Autodesk Fusion 360 part; units mm, degrees
(part 7 of 10)
sketch "Vertical bracket leg sketch (8)" plane through (0, 0, 17) normal (0, 0, 1) x (1, 0, 0) in component "METAL in-bay corner 11R"
  line L0 (215, 200) -> (218, 200)
  line L1 (218, 200) -> (218, 218)
  line L2 (218, 218) -> (215, 218)
  line L3 (215, 218) -> (215, 200)
  dimension "d2836" = 215
  dimension "d2837" = 200
  dimension "d2838" = 3
  dimension "d2839" = 18
  constraint horizontal L0
  constraint vertical L1
  constraint horizontal L2
  constraint vertical L3
  measures "d2836" horizontal distance of origin L0.start
  measures "d2837" vertical distance of origin L0.start
  measures "d2838" horizontal distance of L0.start L0.end
  measures "d2839" vertical distance of L0.end L1.end
extrude "Vertical bracket leg'''''''" add sketch "Vertical bracket leg sketch (8)" along normal blind 16 separate body makes body 92 in component "METAL in-bay corner 11R"
ref_plane "WorkPlane2" through (0, 0, 17) normal (0, 0, 1) x (1, 0, 0) in component "METAL in-bay corner 11R"
sketch "Horizontal bracket leg sketch (8)" plane through (0, 0, 17) normal (0, 0, 1) x (1, 0, 0) in component "METAL in-bay corner 11R"
  line L0 (200, 215) -> (218, 215)
  line L1 (218, 215) -> (218, 218)
  line L2 (218, 218) -> (200, 218)
  line L3 (200, 218) -> (200, 215)
  dimension "d2844" = 200
  dimension "d2845" = 215
  dimension "d2846" = 18
  dimension "d2847" = 3
  constraint horizontal L0
  constraint vertical L1
  constraint horizontal L2
  constraint vertical L3
  measures "d2844" horizontal distance of origin L0.start
  measures "d2845" vertical distance of origin L0.start
  measures "d2846" horizontal distance of L0.start L0.end
  measures "d2847" vertical distance of L0.end L1.end
extrude "Horizontal bracket leg'''''''" add sketch "Horizontal bracket leg sketch (8)" along normal blind 16 bodies 92 in component "METAL in-bay corner 11R"
ref_plane "WorkPlane3" through (218, 0, 0) normal (1, 0, 0) x (0, 1, 0) in component "METAL in-bay corner 11R"
sketch "Vertical rail bolt sketch (8)" plane through (218, 0, 0) normal (1, 0, 0) x (0, 0, -1) in component "METAL in-bay corner 11R"
  circle A0 centre (-25, 206) radius 2.75
  dimension "d2852" = 25
  dimension "d2853" = 206
  dimension "d2854" = 5.5
  measures "d2852" horizontal distance of origin A0.centre
  measures "d2853" vertical distance of origin A0.centre
  measures "d2854" diameter of A0
extrude "Vertical rail bolt'''''''" cut sketch "Vertical rail bolt sketch (8)" against normal blind 3 bodies 92 in component "METAL in-bay corner 11R"
ref_plane "WorkPlane4" through (0, 218, 0) normal (0, 1, 0) x (0, 0, 1) in component "METAL in-bay corner 11R"
sketch "Tie bolt sketch (8)" plane through (0, 218, 0) normal (0, 1, 0) x (1, 0, 0) in component "METAL in-bay corner 11R"
  circle A0 centre (206, -25) radius 2.75
  dimension "d2859" = 206
  dimension "d2860" = 25
  dimension "d2861" = 5.5
  measures "d2859" horizontal distance of origin A0.centre
  measures "d2860" vertical distance of origin A0.centre
  measures "d2861" diameter of A0
extrude "Tie bolt'''''''" cut sketch "Tie bolt sketch (8)" against normal blind 3 bodies 92 in component "METAL in-bay corner 11R"
ref_plane "WorkPlane1" through (215, 0, 0) normal (1, 0, 0) x (0, 1, 0) in component "REFERENCE side M5x8 11R X"
sketch "Button head envelope sketch (24)" plane through (215, 0, 0) normal (1, 0, 0) x (0, 0, -1) in component "REFERENCE side M5x8 11R X"
  circle A0 centre (-25, 206) radius 4.75
  dimension "d2866" = 25
  dimension "d2867" = 206
  dimension "d2868" = 9.5
  measures "d2866" horizontal distance of origin A0.centre
  measures "d2867" vertical distance of origin A0.centre
  measures "d2868" diameter of A0
extrude "Button head envelope'''''''''''''''''''''''" add sketch "Button head envelope sketch (24)" against normal blind 3 separate body makes body 93 in component "REFERENCE side M5x8 11R X"
ref_plane "WorkPlane2" through (215, 0, 0) normal (1, 0, 0) x (0, 1, 0) in component "REFERENCE side M5x8 11R X"
sketch "Shank envelope sketch (24)" plane through (215, 0, 0) normal (1, 0, 0) x (0, 0, -1) in component "REFERENCE side M5x8 11R X"
  circle A0 centre (-25, 206) radius 2.5
  dimension "d2873" = 25
  dimension "d2874" = 206
  dimension "d2875" = 5
  measures "d2873" horizontal distance of origin A0.centre
  measures "d2874" vertical distance of origin A0.centre
  measures "d2875" diameter of A0
extrude "Shank envelope'''''''''''''''''''''''" add sketch "Shank envelope sketch (24)" along normal blind 8 bodies 93 in component "REFERENCE side M5x8 11R X"
ref_plane "WorkPlane1" through (0, 0, 20.6) normal (0, 0, 1) x (1, 0, 0) in component "REFERENCE thin METAL channel nut side 11R X"
sketch "Thin nut envelope sketch (24)" plane through (0, 0, 20.6) normal (0, 0, 1) x (1, 0, 0) in component "REFERENCE thin METAL channel nut side 11R X"
  line L0 (219.5, 200) -> (222.2, 200)
  line L1 (222.2, 200) -> (222.2, 212)
  line L2 (222.2, 212) -> (219.5, 212)
  line L3 (219.5, 212) -> (219.5, 200)
  dimension "d2880" = 219.5
  dimension "d2881" = 200
  dimension "d2882" = 2.7
  dimension "d2883" = 12
  constraint horizontal L0
  constraint vertical L1
  constraint horizontal L2
  constraint vertical L3
  measures "d2880" horizontal distance of origin L0.start
  measures "d2881" vertical distance of origin L0.start
  measures "d2882" horizontal distance of L0.start L0.end
  measures "d2883" vertical distance of L0.end L1.end
extrude "Thin nut envelope'''''''''''''''''''''''" add sketch "Thin nut envelope sketch (24)" along normal blind 8.8 separate body makes body 94 in component "REFERENCE thin METAL channel nut side 11R X"
ref_plane "WorkPlane2" through (219.5, 0, 0) normal (1, 0, 0) x (0, 1, 0) in component "REFERENCE thin METAL channel nut side 11R X"
sketch "Thread envelope sketch (24)" plane through (219.5, 0, 0) normal (1, 0, 0) x (0, 0, -1) in component "REFERENCE thin METAL channel nut side 11R X"
  circle A0 centre (-25, 206) radius 2.6
  dimension "d2888" = 25
  dimension "d2889" = 206
  dimension "d2890" = 5.2
  measures "d2888" horizontal distance of origin A0.centre
  measures "d2889" vertical distance of origin A0.centre
  measures "d2890" diameter of A0
extrude "Thread envelope'''''''''''''''''''''''" cut sketch "Thread envelope sketch (24)" along normal blind 2.7 bodies 94 in component "REFERENCE thin METAL channel nut side 11R X"
ref_plane "WorkPlane1" through (0, 215, 0) normal (0, 1, 0) x (0, 0, 1) in component "REFERENCE side M5x8 11R Y"
sketch "Button head envelope sketch (25)" plane through (0, 215, 0) normal (0, 1, 0) x (1, 0, 0) in component "REFERENCE side M5x8 11R Y"
  circle A0 centre (206, -25) radius 4.75
  dimension "d2895" = 206
  dimension "d2896" = 25
  dimension "d2897" = 9.5
  measures "d2895" horizontal distance of origin A0.centre
  measures "d2896" vertical distance of origin A0.centre
  measures "d2897" diameter of A0
extrude "Button head envelope''''''''''''''''''''''''" add sketch "Button head envelope sketch (25)" against normal blind 3 separate body makes body 95 in component "REFERENCE side M5x8 11R Y"
ref_plane "WorkPlane2" through (0, 215, 0) normal (0, 1, 0) x (0, 0, 1) in component "REFERENCE side M5x8 11R Y"
sketch "Shank envelope sketch (25)" plane through (0, 215, 0) normal (0, 1, 0) x (1, 0, 0) in component "REFERENCE side M5x8 11R Y"
  circle A0 centre (206, -25) radius 2.5
  dimension "d2902" = 206
  dimension "d2903" = 25
  dimension "d2904" = 5
  measures "d2902" horizontal distance of origin A0.centre
  measures "d2903" vertical distance of origin A0.centre
  measures "d2904" diameter of A0
extrude "Shank envelope''''''''''''''''''''''''" add sketch "Shank envelope sketch (25)" along normal blind 8 bodies 95 in component "REFERENCE side M5x8 11R Y"
ref_plane "WorkPlane1" through (0, 0, 20.6) normal (0, 0, 1) x (1, 0, 0) in component "REFERENCE thin METAL channel nut side 11R Y"
sketch "Thin nut envelope sketch (25)" plane through (0, 0, 20.6) normal (0, 0, 1) x (1, 0, 0) in component "REFERENCE thin METAL channel nut side 11R Y"
  line L0 (200, 219.5) -> (212, 219.5)
  line L1 (212, 219.5) -> (212, 222.2)
  line L2 (212, 222.2) -> (200, 222.2)
  line L3 (200, 222.2) -> (200, 219.5)
  dimension "d2909" = 200
  dimension "d2910" = 219.5
  dimension "d2911" = 12
  dimension "d2912" = 2.7
  constraint horizontal L0
  constraint vertical L1
  constraint horizontal L2
  constraint vertical L3
  measures "d2909" horizontal distance of origin L0.start
  measures "d2910" vertical distance of origin L0.start
  measures "d2911" horizontal distance of L0.start L0.end
  measures "d2912" vertical distance of L0.end L1.end
extrude "Thin nut envelope''''''''''''''''''''''''" add sketch "Thin nut envelope sketch (25)" along normal blind 8.8 separate body makes body 96 in component "REFERENCE thin METAL channel nut side 11R Y"
ref_plane "WorkPlane2" through (0, 219.5, 0) normal (0, 1, 0) x (0, 0, 1) in component "REFERENCE thin METAL channel nut side 11R Y"
sketch "Thread envelope sketch (25)" plane through (0, 219.5, 0) normal (0, 1, 0) x (1, 0, 0) in component "REFERENCE thin METAL channel nut side 11R Y"
  circle A0 centre (206, -25) radius 2.6
  dimension "d2917" = 206
  dimension "d2918" = 25
  dimension "d2919" = 5.2
  measures "d2917" horizontal distance of origin A0.centre
  measures "d2918" vertical distance of origin A0.centre
  measures "d2919" diameter of A0
extrude "Thread envelope''''''''''''''''''''''''" cut sketch "Thread envelope sketch (25)" along normal blind 2.7 bodies 96 in component "REFERENCE thin METAL channel nut side 11R Y"
ref_plane "WorkPlane1" through (0, 0, 15) normal (0, 0, 1) x (1, 0, 0) in component "METAL flush wall tab 00"
sketch "Side attachment leg sketch" plane through (0, 0, 15) normal (0, 0, 1) x (1, 0, 0) in component "METAL flush wall tab 00"
  line L0 (22, 68) -> (25, 68)
  line L1 (25, 68) -> (25, 92)
  line L2 (25, 92) -> (22, 92)
  line L3 (22, 92) -> (22, 68)
  dimension "d2924" = 22
  dimension "d2925" = 68
  dimension "d2926" = 3
  dimension "d2927" = 24
  constraint horizontal L0
  constraint vertical L1
  constraint horizontal L2
  constraint vertical L3
  measures "d2924" horizontal distance of origin L0.start
  measures "d2925" vertical distance of origin L0.start
  measures "d2926" horizontal distance of L0.start L0.end
  measures "d2927" vertical distance of L0.end L1.end
extrude "Side attachment leg" add sketch "Side attachment leg sketch" along normal blind 20 separate body makes body 97 in component "METAL flush wall tab 00"
ref_plane "WorkPlane2" through (0, 0, 32) normal (0, 0, 1) x (1, 0, 0) in component "METAL flush wall tab 00"
sketch "Flush wall foot sketch" plane through (0, 0, 32) normal (0, 0, 1) x (1, 0, 0) in component "METAL flush wall tab 00"
  line L0 (22, 68) -> (44, 68)
  line L1 (44, 68) -> (44, 92)
  line L2 (44, 92) -> (22, 92)
  line L3 (22, 92) -> (22, 68)
  dimension "d2932" = 22
  dimension "d2933" = 68
  dimension "d2934" = 22
  dimension "d2935" = 24
  constraint horizontal L0
  constraint vertical L1
  constraint horizontal L2
  constraint vertical L3
  measures "d2932" horizontal distance of origin L0.start
  measures "d2933" vertical distance of origin L0.start
  measures "d2934" horizontal distance of L0.start L0.end
  measures "d2935" vertical distance of L0.end L1.end
extrude "Flush wall foot" add sketch "Flush wall foot sketch" along normal blind 3 bodies 97 in component "METAL flush wall tab 00"
ref_plane "WorkPlane3" through (22, 0, 0) normal (1, 0, 0) x (0, 1, 0) in component "METAL flush wall tab 00"
sketch "Side fixing sketch" plane through (22, 0, 0) normal (1, 0, 0) x (0, 0, -1) in component "METAL flush wall tab 00"
  circle A0 centre (-25, 74) radius 2.75
  dimension "d2940" = 25
  dimension "d2941" = 74
  dimension "d2942" = 5.5
  measures "d2940" horizontal distance of origin A0.centre
  measures "d2941" vertical distance of origin A0.centre
  measures "d2942" diameter of A0
extrude "Side fixing" cut sketch "Side fixing sketch" along normal blind 3 bodies 97 in component "METAL flush wall tab 00"
ref_plane "WorkPlane1" through (25, 0, 0) normal (1, 0, 0) x (0, 1, 0) in component "REFERENCE side M5x8 wall 000"
sketch "Button head envelope sketch (26)" plane through (25, 0, 0) normal (1, 0, 0) x (0, 0, -1) in component "REFERENCE side M5x8 wall 000"
  circle A0 centre (-25, 74) radius 4.75
  dimension "d2947" = 25
  dimension "d2948" = 74
  dimension "d2949" = 9.5
  measures "d2947" horizontal distance of origin A0.centre
  measures "d2948" vertical distance of origin A0.centre
  measures "d2949" diameter of A0
extrude "Button head envelope'''''''''''''''''''''''''" add sketch "Button head envelope sketch (26)" along normal blind 3 separate body makes body 98 in component "REFERENCE side M5x8 wall 000"
ref_plane "WorkPlane2" through (25, 0, 0) normal (1, 0, 0) x (0, 1, 0) in component "REFERENCE side M5x8 wall 000"
sketch "Shank envelope sketch (26)" plane through (25, 0, 0) normal (1, 0, 0) x (0, 0, -1) in component "REFERENCE side M5x8 wall 000"
  circle A0 centre (-25, 74) radius 2.5
  dimension "d2954" = 25
  dimension "d2955" = 74
  dimension "d2956" = 5
  measures "d2954" horizontal distance of origin A0.centre
  measures "d2955" vertical distance of origin A0.centre
  measures "d2956" diameter of A0
extrude "Shank envelope'''''''''''''''''''''''''" add sketch "Shank envelope sketch (26)" against normal blind 8 bodies 98 in component "REFERENCE side M5x8 wall 000"
ref_plane "WorkPlane1" through (0, 0, 20.6) normal (0, 0, 1) x (1, 0, 0) in component "REFERENCE thin METAL channel nut side wall 000"
sketch "Thin nut envelope sketch (26)" plane through (0, 0, 20.6) normal (0, 0, 1) x (1, 0, 0) in component "REFERENCE thin METAL channel nut side wall 000"
  line L0 (17.8, 68) -> (20.5, 68)
  line L1 (20.5, 68) -> (20.5, 80)
  line L2 (20.5, 80) -> (17.8, 80)
  line L3 (17.8, 80) -> (17.8, 68)
  dimension "d2961" = 17.8
  dimension "d2962" = 68
  dimension "d2963" = 2.7
  dimension "d2964" = 12
  constraint horizontal L0
  constraint vertical L1
  constraint horizontal L2
  constraint vertical L3
  measures "d2961" horizontal distance of origin L0.start
  measures "d2962" vertical distance of origin L0.start
  measures "d2963" horizontal distance of L0.start L0.end
  measures "d2964" vertical distance of L0.end L1.end
extrude "Thin nut envelope'''''''''''''''''''''''''" add sketch "Thin nut envelope sketch (26)" along normal blind 8.8 separate body makes body 99 in component "REFERENCE thin METAL channel nut side wall 000"
ref_plane "WorkPlane2" through (17.8, 0, 0) normal (1, 0, 0) x (0, 1, 0) in component "REFERENCE thin METAL channel nut side wall 000"
sketch "Thread envelope sketch (26)" plane through (17.8, 0, 0) normal (1, 0, 0) x (0, 0, -1) in component "REFERENCE thin METAL channel nut side wall 000"
  circle A0 centre (-25, 74) radius 2.6
  dimension "d2969" = 25
  dimension "d2970" = 74
  dimension "d2971" = 5.2
  measures "d2969" horizontal distance of origin A0.centre
  measures "d2970" vertical distance of origin A0.centre
  measures "d2971" diameter of A0
extrude "Thread envelope'''''''''''''''''''''''''" cut sketch "Thread envelope sketch (26)" along normal blind 2.7 bodies 99 in component "REFERENCE thin METAL channel nut side wall 000"
ref_plane "WorkPlane4" through (22, 0, 0) normal (1, 0, 0) x (0, 1, 0) in component "METAL flush wall tab 00"
sketch "Side fixing sketch (1)" plane through (22, 0, 0) normal (1, 0, 0) x (0, 0, -1) in component "METAL flush wall tab 00"
  circle A0 centre (-25, 86) radius 2.75
  dimension "d2976" = 25
  dimension "d2977" = 86
  dimension "d2978" = 5.5
  measures "d2976" horizontal distance of origin A0.centre
  measures "d2977" vertical distance of origin A0.centre
  measures "d2978" diameter of A0
extrude "Side fixing (1)" cut sketch "Side fixing sketch (1)" along normal blind 3 bodies 97 in component "METAL flush wall tab 00"
ref_plane "WorkPlane1" through (25, 0, 0) normal (1, 0, 0) x (0, 1, 0) in component "REFERENCE side M5x8 wall 001"
sketch "Button head envelope sketch (27)" plane through (25, 0, 0) normal (1, 0, 0) x (0, 0, -1) in component "REFERENCE side M5x8 wall 001"
  circle A0 centre (-25, 86) radius 4.75
  dimension "d2983" = 25
  dimension "d2984" = 86
  dimension "d2985" = 9.5
  measures "d2983" horizontal distance of origin A0.centre
  measures "d2984" vertical distance of origin A0.centre
  measures "d2985" diameter of A0
extrude "Button head envelope''''''''''''''''''''''''''" add sketch "Button head envelope sketch (27)" along normal blind 3 separate body makes body 100 in component "REFERENCE side M5x8 wall 001"
ref_plane "WorkPlane2" through (25, 0, 0) normal (1, 0, 0) x (0, 1, 0) in component "REFERENCE side M5x8 wall 001"
sketch "Shank envelope sketch (27)" plane through (25, 0, 0) normal (1, 0, 0) x (0, 0, -1) in component "REFERENCE side M5x8 wall 001"
  circle A0 centre (-25, 86) radius 2.5
  dimension "d2990" = 25
  dimension "d2991" = 86
  dimension "d2992" = 5
  measures "d2990" horizontal distance of origin A0.centre
  measures "d2991" vertical distance of origin A0.centre
  measures "d2992" diameter of A0
extrude "Shank envelope''''''''''''''''''''''''''" add sketch "Shank envelope sketch (27)" against normal blind 8 bodies 100 in component "REFERENCE side M5x8 wall 001"
ref_plane "WorkPlane1" through (0, 0, 20.6) normal (0, 0, 1) x (1, 0, 0) in component "REFERENCE thin METAL channel nut side wall 001"
sketch "Thin nut envelope sketch (27)" plane through (0, 0, 20.6) normal (0, 0, 1) x (1, 0, 0) in component "REFERENCE thin METAL channel nut side wall 001"
  line L0 (17.8, 80) -> (20.5, 80)
  line L1 (20.5, 80) -> (20.5, 92)
  line L2 (20.5, 92) -> (17.8, 92)
  line L3 (17.8, 92) -> (17.8, 80)
  dimension "d2997" = 17.8
  dimension "d2998" = 80
  dimension "d2999" = 2.7
  dimension "d3000" = 12
  constraint horizontal L0
  constraint vertical L1
  constraint horizontal L2
  constraint vertical L3
  measures "d2997" horizontal distance of origin L0.start
  measures "d2998" vertical distance of origin L0.start
  measures "d2999" horizontal distance of L0.start L0.end
  measures "d3000" vertical distance of L0.end L1.end
extrude "Thin nut envelope''''''''''''''''''''''''''" add sketch "Thin nut envelope sketch (27)" along normal blind 8.8 separate body makes body 101 in component "REFERENCE thin METAL channel nut side wall 001"
ref_plane "WorkPlane2" through (17.8, 0, 0) normal (1, 0, 0) x (0, 1, 0) in component "REFERENCE thin METAL channel nut side wall 001"
sketch "Thread envelope sketch (27)" plane through (17.8, 0, 0) normal (1, 0, 0) x (0, 0, -1) in component "REFERENCE thin METAL channel nut side wall 001"
  circle A0 centre (-25, 86) radius 2.6
  dimension "d3005" = 25
  dimension "d3006" = 86
  dimension "d3007" = 5.2
  measures "d3005" horizontal distance of origin A0.centre
  measures "d3006" vertical distance of origin A0.centre
  measures "d3007" diameter of A0
extrude "Thread envelope''''''''''''''''''''''''''" cut sketch "Thread envelope sketch (27)" along normal blind 2.7 bodies 101 in component "REFERENCE thin METAL channel nut side wall 001"
ref_plane "WorkPlane5" through (0, 0, 32) normal (0, 0, 1) x (1, 0, 0) in component "METAL flush wall tab 00"
sketch "Wall anchor clearance sketch" plane through (0, 0, 32) normal (0, 0, 1) x (1, 0, 0) in component "METAL flush wall tab 00"
  circle A0 centre (35, 80) radius 3.25
  dimension "d3012" = 35
  dimension "d3013" = 80
  dimension "d3014" = 6.5
  measures "d3012" horizontal distance of origin A0.centre
  measures "d3013" vertical distance of origin A0.centre
  measures "d3014" diameter of A0
extrude "Wall anchor clearance" cut sketch "Wall anchor clearance sketch" along normal blind 3 bodies 97 in component "METAL flush wall tab 00"
ref_plane "WorkPlane1" through (0, 0, 29) normal (0, 0, 1) x (1, 0, 0) in component "REFERENCE wall anchor HEAD ONLY 00"
sketch "Anchor head envelope sketch" plane through (0, 0, 29) normal (0, 0, 1) x (1, 0, 0) in component "REFERENCE wall anchor HEAD ONLY 00"
  circle A0 centre (35, 80) radius 6
  dimension "d3019" = 35
  dimension "d3020" = 80
  dimension "d3021" = 12
  measures "d3019" horizontal distance of origin A0.centre
  measures "d3020" vertical distance of origin A0.centre
  measures "d3021" diameter of A0
extrude "Anchor head envelope" add sketch "Anchor head envelope sketch" along normal blind 3 separate body makes body 102 in component "REFERENCE wall anchor HEAD ONLY 00"
ref_plane "WorkPlane2" through (0, 0, 32) normal (0, 0, 1) x (1, 0, 0) in component "REFERENCE wall anchor HEAD ONLY 00"
sketch "Clearance shank only - anchor not selected sketch" plane through (0, 0, 32) normal (0, 0, 1) x (1, 0, 0) in component "REFERENCE wall anchor HEAD ONLY 00"
  circle A0 centre (35, 80) radius 3
  dimension "d3026" = 35
  dimension "d3027" = 80
  dimension "d3028" = 6
  measures "d3026" horizontal distance of origin A0.centre
  measures "d3027" vertical distance of origin A0.centre
  measures "d3028" diameter of A0
extrude "Clearance shank only - anchor not selected" add sketch "Clearance shank only - anchor not selected sketch" along normal blind 3 bodies 102 in component "REFERENCE wall anchor HEAD ONLY 00"
ref_plane "WorkPlane1" through (0, 0, 15) normal (0, 0, 1) x (1, 0, 0) in component "METAL flush wall tab 01"
sketch "Side attachment leg sketch (2)" plane through (0, 0, 15) normal (0, 0, 1) x (1, 0, 0) in component "METAL flush wall tab 01"
  line L0 (22, 148) -> (25, 148)
  line L1 (25, 148) -> (25, 172)
  line L2 (25, 172) -> (22, 172)
  line L3 (22, 172) -> (22, 148)
  dimension "d3033" = 22
  dimension "d3034" = 148
  dimension "d3035" = 3
  dimension "d3036" = 24
  constraint horizontal L0
  constraint vertical L1
  constraint horizontal L2
  constraint vertical L3
  measures "d3033" horizontal distance of origin L0.start
  measures "d3034" vertical distance of origin L0.start
  measures "d3035" horizontal distance of L0.start L0.end
  measures "d3036" vertical distance of L0.end L1.end
extrude "Side attachment leg'" add sketch "Side attachment leg sketch (2)" along normal blind 20 separate body makes body 103 in component "METAL flush wall tab 01"
ref_plane "WorkPlane2" through (0, 0, 32) normal (0, 0, 1) x (1, 0, 0) in component "METAL flush wall tab 01"
sketch "Flush wall foot sketch (2)" plane through (0, 0, 32) normal (0, 0, 1) x (1, 0, 0) in component "METAL flush wall tab 01"
  line L0 (22, 148) -> (44, 148)
  line L1 (44, 148) -> (44, 172)
  line L2 (44, 172) -> (22, 172)
  line L3 (22, 172) -> (22, 148)
  dimension "d3041" = 22
  dimension "d3042" = 148
  dimension "d3043" = 22
  dimension "d3044" = 24
  constraint horizontal L0
  constraint vertical L1
  constraint horizontal L2
  constraint vertical L3
  measures "d3041" horizontal distance of origin L0.start
  measures "d3042" vertical distance of origin L0.start
  measures "d3043" horizontal distance of L0.start L0.end
  measures "d3044" vertical distance of L0.end L1.end
extrude "Flush wall foot'" add sketch "Flush wall foot sketch (2)" along normal blind 3 bodies 103 in component "METAL flush wall tab 01"
ref_plane "WorkPlane3" through (22, 0, 0) normal (1, 0, 0) x (0, 1, 0) in component "METAL flush wall tab 01"
sketch "Side fixing sketch (2)" plane through (22, 0, 0) normal (1, 0, 0) x (0, 0, -1) in component "METAL flush wall tab 01"
  circle A0 centre (-25, 154) radius 2.75
  dimension "d3049" = 25
  dimension "d3050" = 154
  dimension "d3051" = 5.5
  measures "d3049" horizontal distance of origin A0.centre
  measures "d3050" vertical distance of origin A0.centre
  measures "d3051" diameter of A0
extrude "Side fixing'" cut sketch "Side fixing sketch (2)" along normal blind 3 bodies 103 in component "METAL flush wall tab 01"
ref_plane "WorkPlane1" through (25, 0, 0) normal (1, 0, 0) x (0, 1, 0) in component "REFERENCE side M5x8 wall 010"
sketch "Button head envelope sketch (28)" plane through (25, 0, 0) normal (1, 0, 0) x (0, 0, -1) in component "REFERENCE side M5x8 wall 010"
  circle A0 centre (-25, 154) radius 4.75
  dimension "d3056" = 25
  dimension "d3057" = 154
  dimension "d3058" = 9.5
  measures "d3056" horizontal distance of origin A0.centre
  measures "d3057" vertical distance of origin A0.centre
  measures "d3058" diameter of A0
extrude "Button head envelope'''''''''''''''''''''''''''" add sketch "Button head envelope sketch (28)" along normal blind 3 separate body makes body 104 in component "REFERENCE side M5x8 wall 010"
ref_plane "WorkPlane2" through (25, 0, 0) normal (1, 0, 0) x (0, 1, 0) in component "REFERENCE side M5x8 wall 010"
sketch "Shank envelope sketch (28)" plane through (25, 0, 0) normal (1, 0, 0) x (0, 0, -1) in component "REFERENCE side M5x8 wall 010"
  circle A0 centre (-25, 154) radius 2.5
  dimension "d3063" = 25
  dimension "d3064" = 154
  dimension "d3065" = 5
  measures "d3063" horizontal distance of origin A0.centre
  measures "d3064" vertical distance of origin A0.centre
  measures "d3065" diameter of A0
extrude "Shank envelope'''''''''''''''''''''''''''" add sketch "Shank envelope sketch (28)" against normal blind 8 bodies 104 in component "REFERENCE side M5x8 wall 010"
ref_plane "WorkPlane1" through (0, 0, 20.6) normal (0, 0, 1) x (1, 0, 0) in component "REFERENCE thin METAL channel nut side wall 010"
sketch "Thin nut envelope sketch (28)" plane through (0, 0, 20.6) normal (0, 0, 1) x (1, 0, 0) in component "REFERENCE thin METAL channel nut side wall 010"
  line L0 (17.8, 148) -> (20.5, 148)
  line L1 (20.5, 148) -> (20.5, 160)
  line L2 (20.5, 160) -> (17.8, 160)
  line L3 (17.8, 160) -> (17.8, 148)
  dimension "d3070" = 17.8
  dimension "d3071" = 148
  dimension "d3072" = 2.7
  dimension "d3073" = 12
  constraint horizontal L0
  constraint vertical L1
  constraint horizontal L2
  constraint vertical L3
  measures "d3070" horizontal distance of origin L0.start
  measures "d3071" vertical distance of origin L0.start
  measures "d3072" horizontal distance of L0.start L0.end
  measures "d3073" vertical distance of L0.end L1.end
extrude "Thin nut envelope'''''''''''''''''''''''''''" add sketch "Thin nut envelope sketch (28)" along normal blind 8.8 separate body makes body 105 in component "REFERENCE thin METAL channel nut side wall 010"
ref_plane "WorkPlane2" through (17.8, 0, 0) normal (1, 0, 0) x (0, 1, 0) in component "REFERENCE thin METAL channel nut side wall 010"
sketch "Thread envelope sketch (28)" plane through (17.8, 0, 0) normal (1, 0, 0) x (0, 0, -1) in component "REFERENCE thin METAL channel nut side wall 010"
  circle A0 centre (-25, 154) radius 2.6
  dimension "d3078" = 25
  dimension "d3079" = 154
  dimension "d3080" = 5.2
  measures "d3078" horizontal distance of origin A0.centre
  measures "d3079" vertical distance of origin A0.centre
  measures "d3080" diameter of A0
extrude "Thread envelope'''''''''''''''''''''''''''" cut sketch "Thread envelope sketch (28)" along normal blind 2.7 bodies 105 in component "REFERENCE thin METAL channel nut side wall 010"
ref_plane "WorkPlane4" through (22, 0, 0) normal (1, 0, 0) x (0, 1, 0) in component "METAL flush wall tab 01"
sketch "Side fixing sketch (1) (2)" plane through (22, 0, 0) normal (1, 0, 0) x (0, 0, -1) in component "METAL flush wall tab 01"
  circle A0 centre (-25, 166) radius 2.75
  dimension "d3085" = 25
  dimension "d3086" = 166
  dimension "d3087" = 5.5
  measures "d3085" horizontal distance of origin A0.centre
  measures "d3086" vertical distance of origin A0.centre
  measures "d3087" diameter of A0
extrude "Side fixing (1)'" cut sketch "Side fixing sketch (1) (2)" along normal blind 3 bodies 103 in component "METAL flush wall tab 01"
ref_plane "WorkPlane1" through (25, 0, 0) normal (1, 0, 0) x (0, 1, 0) in component "REFERENCE side M5x8 wall 011"
sketch "Button head envelope sketch (29)" plane through (25, 0, 0) normal (1, 0, 0) x (0, 0, -1) in component "REFERENCE side M5x8 wall 011"
  circle A0 centre (-25, 166) radius 4.75
  dimension "d3092" = 25
  dimension "d3093" = 166
  dimension "d3094" = 9.5
  measures "d3092" horizontal distance of origin A0.centre
  measures "d3093" vertical distance of origin A0.centre
  measures "d3094" diameter of A0
extrude "Button head envelope''''''''''''''''''''''''''''" add sketch "Button head envelope sketch (29)" along normal blind 3 separate body makes body 106 in component "REFERENCE side M5x8 wall 011"
ref_plane "WorkPlane2" through (25, 0, 0) normal (1, 0, 0) x (0, 1, 0) in component "REFERENCE side M5x8 wall 011"
sketch "Shank envelope sketch (29)" plane through (25, 0, 0) normal (1, 0, 0) x (0, 0, -1) in component "REFERENCE side M5x8 wall 011"
  circle A0 centre (-25, 166) radius 2.5
  dimension "d3099" = 25
  dimension "d3100" = 166
  dimension "d3101" = 5
  measures "d3099" horizontal distance of origin A0.centre
  measures "d3100" vertical distance of origin A0.centre
  measures "d3101" diameter of A0
extrude "Shank envelope''''''''''''''''''''''''''''" add sketch "Shank envelope sketch (29)" against normal blind 8 bodies 106 in component "REFERENCE side M5x8 wall 011"
ref_plane "WorkPlane1" through (0, 0, 20.6) normal (0, 0, 1) x (1, 0, 0) in component "REFERENCE thin METAL channel nut side wall 011"
sketch "Thin nut envelope sketch (29)" plane through (0, 0, 20.6) normal (0, 0, 1) x (1, 0, 0) in component "REFERENCE thin METAL channel nut side wall 011"
  line L0 (17.8, 160) -> (20.5, 160)
  line L1 (20.5, 160) -> (20.5, 172)
  line L2 (20.5, 172) -> (17.8, 172)
  line L3 (17.8, 172) -> (17.8, 160)
  dimension "d3106" = 17.8
  dimension "d3107" = 160
  dimension "d3108" = 2.7
  dimension "d3109" = 12
  constraint horizontal L0
  constraint vertical L1
  constraint horizontal L2
  constraint vertical L3
  measures "d3106" horizontal distance of origin L0.start
  measures "d3107" vertical distance of origin L0.start
  measures "d3108" horizontal distance of L0.start L0.end
  measures "d3109" vertical distance of L0.end L1.end
extrude "Thin nut envelope''''''''''''''''''''''''''''" add sketch "Thin nut envelope sketch (29)" along normal blind 8.8 separate body makes body 107 in component "REFERENCE thin METAL channel nut side wall 011"
ref_plane "WorkPlane2" through (17.8, 0, 0) normal (1, 0, 0) x (0, 1, 0) in component "REFERENCE thin METAL channel nut side wall 011"
sketch "Thread envelope sketch (29)" plane through (17.8, 0, 0) normal (1, 0, 0) x (0, 0, -1) in component "REFERENCE thin METAL channel nut side wall 011"
  circle A0 centre (-25, 166) radius 2.6
  dimension "d3114" = 25
  dimension "d3115" = 166
  dimension "d3116" = 5.2
  measures "d3114" horizontal distance of origin A0.centre
  measures "d3115" vertical distance of origin A0.centre
  measures "d3116" diameter of A0
extrude "Thread envelope''''''''''''''''''''''''''''" cut sketch "Thread envelope sketch (29)" along normal blind 2.7 bodies 107 in component "REFERENCE thin METAL channel nut side wall 011"
ref_plane "WorkPlane5" through (0, 0, 32) normal (0, 0, 1) x (1, 0, 0) in component "METAL flush wall tab 01"
sketch "Wall anchor clearance sketch (2)" plane through (0, 0, 32) normal (0, 0, 1) x (1, 0, 0) in component "METAL flush wall tab 01"
  circle A0 centre (35, 160) radius 3.25
  dimension "d3121" = 35
  dimension "d3122" = 160
  dimension "d3123" = 6.5
  measures "d3121" horizontal distance of origin A0.centre
  measures "d3122" vertical distance of origin A0.centre
  measures "d3123" diameter of A0
extrude "Wall anchor clearance'" cut sketch "Wall anchor clearance sketch (2)" along normal blind 3 bodies 103 in component "METAL flush wall tab 01"
ref_plane "WorkPlane1" through (0, 0, 29) normal (0, 0, 1) x (1, 0, 0) in component "REFERENCE wall anchor HEAD ONLY 01"
sketch "Anchor head envelope sketch (2)" plane through (0, 0, 29) normal (0, 0, 1) x (1, 0, 0) in component "REFERENCE wall anchor HEAD ONLY 01"
  circle A0 centre (35, 160) radius 6
  dimension "d3128" = 35
  dimension "d3129" = 160
  dimension "d3130" = 12
  measures "d3128" horizontal distance of origin A0.centre
  measures "d3129" vertical distance of origin A0.centre
  measures "d3130" diameter of A0
extrude "Anchor head envelope'" add sketch "Anchor head envelope sketch (2)" along normal blind 3 separate body makes body 108 in component "REFERENCE wall anchor HEAD ONLY 01"
ref_plane "WorkPlane2" through (0, 0, 32) normal (0, 0, 1) x (1, 0, 0) in component "REFERENCE wall anchor HEAD ONLY 01"
sketch "Clearance shank only - anchor not selected sketch (2)" plane through (0, 0, 32) normal (0, 0, 1) x (1, 0, 0) in component "REFERENCE wall anchor HEAD ONLY 01"
  circle A0 centre (35, 160) radius 3
  dimension "d3135" = 35
  dimension "d3136" = 160
  dimension "d3137" = 6
  measures "d3135" horizontal distance of origin A0.centre
  measures "d3136" vertical distance of origin A0.centre
  measures "d3137" diameter of A0
extrude "Clearance shank only - anchor not selected'" add sketch "Clearance shank only - anchor not selected sketch (2)" along normal blind 3 bodies 108 in component "REFERENCE wall anchor HEAD ONLY 01"
ref_plane "WorkPlane1" through (0, 0, 15) normal (0, 0, 1) x (1, 0, 0) in component "METAL flush wall tab 10"
sketch "Side attachment leg sketch (3)" plane through (0, 0, 15) normal (0, 0, 1) x (1, 0, 0) in component "METAL flush wall tab 10"
  line L0 (215, 68) -> (218, 68)
  line L1 (218, 68) -> (218, 92)
  line L2 (218, 92) -> (215, 92)
  line L3 (215, 92) -> (215, 68)
  dimension "d3142" = 215
  dimension "d3143" = 68
  dimension "d3144" = 3
  dimension "d3145" = 24
  constraint horizontal L0
  constraint vertical L1
  constraint horizontal L2
  constraint vertical L3
  measures "d3142" horizontal distance of origin L0.start
  measures "d3143" vertical distance of origin L0.start
  measures "d3144" horizontal distance of L0.start L0.end
  measures "d3145" vertical distance of L0.end L1.end
extrude "Side attachment leg''" add sketch "Side attachment leg sketch (3)" along normal blind 20 separate body makes body 109 in component "METAL flush wall tab 10"
ref_plane "WorkPlane2" through (0, 0, 32) normal (0, 0, 1) x (1, 0, 0) in component "METAL flush wall tab 10"
sketch "Flush wall foot sketch (3)" plane through (0, 0, 32) normal (0, 0, 1) x (1, 0, 0) in component "METAL flush wall tab 10"
  line L0 (196, 68) -> (218, 68)
  line L1 (218, 68) -> (218, 92)
  line L2 (218, 92) -> (196, 92)
  line L3 (196, 92) -> (196, 68)
  dimension "d3150" = 196
  dimension "d3151" = 68
  dimension "d3152" = 22
  dimension "d3153" = 24
  constraint horizontal L0
  constraint vertical L1
  constraint horizontal L2
  constraint vertical L3
  measures "d3150" horizontal distance of origin L0.start
  measures "d3151" vertical distance of origin L0.start
  measures "d3152" horizontal distance of L0.start L0.end
  measures "d3153" vertical distance of L0.end L1.end
extrude "Flush wall foot''" add sketch "Flush wall foot sketch (3)" along normal blind 3 bodies 109 in component "METAL flush wall tab 10"
ref_plane "WorkPlane3" through (218, 0, 0) normal (1, 0, 0) x (0, 1, 0) in component "METAL flush wall tab 10"
sketch "Side fixing sketch (3)" plane through (218, 0, 0) normal (1, 0, 0) x (0, 0, -1) in component "METAL flush wall tab 10"
  circle A0 centre (-25, 74) radius 2.75
  dimension "d3158" = 25
  dimension "d3159" = 74
  dimension "d3160" = 5.5
  measures "d3158" horizontal distance of origin A0.centre
  measures "d3159" vertical distance of origin A0.centre
  measures "d3160" diameter of A0
extrude "Side fixing''" cut sketch "Side fixing sketch (3)" against normal blind 3 bodies 109 in component "METAL flush wall tab 10"
ref_plane "WorkPlane1" through (215, 0, 0) normal (1, 0, 0) x (0, 1, 0) in component "REFERENCE side M5x8 wall 100"
sketch "Button head envelope sketch (30)" plane through (215, 0, 0) normal (1, 0, 0) x (0, 0, -1) in component "REFERENCE side M5x8 wall 100"
  circle A0 centre (-25, 74) radius 4.75
  dimension "d3165" = 25
  dimension "d3166" = 74
  dimension "d3167" = 9.5
  measures "d3165" horizontal distance of origin A0.centre
  measures "d3166" vertical distance of origin A0.centre
  measures "d3167" diameter of A0
extrude "Button head envelope'''''''''''''''''''''''''''''" add sketch "Button head envelope sketch (30)" against normal blind 3 separate body makes body 110 in component "REFERENCE side M5x8 wall 100"
ref_plane "WorkPlane2" through (215, 0, 0) normal (1, 0, 0) x (0, 1, 0) in component "REFERENCE side M5x8 wall 100"
sketch "Shank envelope sketch (30)" plane through (215, 0, 0) normal (1, 0, 0) x (0, 0, -1) in component "REFERENCE side M5x8 wall 100"
  circle A0 centre (-25, 74) radius 2.5
  dimension "d3172" = 25
  dimension "d3173" = 74
  dimension "d3174" = 5
  measures "d3172" horizontal distance of origin A0.centre
  measures "d3173" vertical distance of origin A0.centre
  measures "d3174" diameter of A0
extrude "Shank envelope'''''''''''''''''''''''''''''" add sketch "Shank envelope sketch (30)" along normal blind 8 bodies 110 in component "REFERENCE side M5x8 wall 100"
ref_plane "WorkPlane1" through (0, 0, 20.6) normal (0, 0, 1) x (1, 0, 0) in component "REFERENCE thin METAL channel nut side wall 100"
sketch "Thin nut envelope sketch (30)" plane through (0, 0, 20.6) normal (0, 0, 1) x (1, 0, 0) in component "REFERENCE thin METAL channel nut side wall 100"
  line L0 (219.5, 68) -> (222.2, 68)
  line L1 (222.2, 68) -> (222.2, 80)
  line L2 (222.2, 80) -> (219.5, 80)
  line L3 (219.5, 80) -> (219.5, 68)
  dimension "d3179" = 219.5
  dimension "d3180" = 68
  dimension "d3181" = 2.7
  dimension "d3182" = 12
  constraint horizontal L0
  constraint vertical L1
  constraint horizontal L2
  constraint vertical L3
  measures "d3179" horizontal distance of origin L0.start
  measures "d3180" vertical distance of origin L0.start
  measures "d3181" horizontal distance of L0.start L0.end
  measures "d3182" vertical distance of L0.end L1.end
extrude "Thin nut envelope'''''''''''''''''''''''''''''" add sketch "Thin nut envelope sketch (30)" along normal blind 8.8 separate body makes body 111 in component "REFERENCE thin METAL channel nut side wall 100"
ref_plane "WorkPlane2" through (219.5, 0, 0) normal (1, 0, 0) x (0, 1, 0) in component "REFERENCE thin METAL channel nut side wall 100"
sketch "Thread envelope sketch (30)" plane through (219.5, 0, 0) normal (1, 0, 0) x (0, 0, -1) in component "REFERENCE thin METAL channel nut side wall 100"
  circle A0 centre (-25, 74) radius 2.6
  dimension "d3187" = 25
  dimension "d3188" = 74
  dimension "d3189" = 5.2
  measures "d3187" horizontal distance of origin A0.centre
  measures "d3188" vertical distance of origin A0.centre
  measures "d3189" diameter of A0
extrude "Thread envelope'''''''''''''''''''''''''''''" cut sketch "Thread envelope sketch (30)" along normal blind 2.7 bodies 111 in component "REFERENCE thin METAL channel nut side wall 100"
ref_plane "WorkPlane4" through (218, 0, 0) normal (1, 0, 0) x (0, 1, 0) in component "METAL flush wall tab 10"
sketch "Side fixing sketch (1) (3)" plane through (218, 0, 0) normal (1, 0, 0) x (0, 0, -1) in component "METAL flush wall tab 10"
  circle A0 centre (-25, 86) radius 2.75
  dimension "d3194" = 25
  dimension "d3195" = 86
  dimension "d3196" = 5.5
  measures "d3194" horizontal distance of origin A0.centre
  measures "d3195" vertical distance of origin A0.centre
  measures "d3196" diameter of A0
extrude "Side fixing (1)''" cut sketch "Side fixing sketch (1) (3)" against normal blind 3 bodies 109 in component "METAL flush wall tab 10"
ref_plane "WorkPlane1" through (215, 0, 0) normal (1, 0, 0) x (0, 1, 0) in component "REFERENCE side M5x8 wall 101"
sketch "Button head envelope sketch (31)" plane through (215, 0, 0) normal (1, 0, 0) x (0, 0, -1) in component "REFERENCE side M5x8 wall 101"
  circle A0 centre (-25, 86) radius 4.75
  dimension "d3201" = 25
  dimension "d3202" = 86
  dimension "d3203" = 9.5
  measures "d3201" horizontal distance of origin A0.centre
  measures "d3202" vertical distance of origin A0.centre
  measures "d3203" diameter of A0
extrude "Button head envelope''''''''''''''''''''''''''''''" add sketch "Button head envelope sketch (31)" against normal blind 3 separate body makes body 112 in component "REFERENCE side M5x8 wall 101"
ref_plane "WorkPlane2" through (215, 0, 0) normal (1, 0, 0) x (0, 1, 0) in component "REFERENCE side M5x8 wall 101"
sketch "Shank envelope sketch (31)" plane through (215, 0, 0) normal (1, 0, 0) x (0, 0, -1) in component "REFERENCE side M5x8 wall 101"
  circle A0 centre (-25, 86) radius 2.5
  dimension "d3208" = 25
  dimension "d3209" = 86
  dimension "d3210" = 5
  measures "d3208" horizontal distance of origin A0.centre
  measures "d3209" vertical distance of origin A0.centre
  measures "d3210" diameter of A0
extrude "Shank envelope''''''''''''''''''''''''''''''" add sketch "Shank envelope sketch (31)" along normal blind 8 bodies 112 in component "REFERENCE side M5x8 wall 101"
ref_plane "WorkPlane1" through (0, 0, 20.6) normal (0, 0, 1) x (1, 0, 0) in component "REFERENCE thin METAL channel nut side wall 101"
sketch "Thin nut envelope sketch (31)" plane through (0, 0, 20.6) normal (0, 0, 1) x (1, 0, 0) in component "REFERENCE thin METAL channel nut side wall 101"
  line L0 (219.5, 80) -> (222.2, 80)
  line L1 (222.2, 80) -> (222.2, 92)
  line L2 (222.2, 92) -> (219.5, 92)
  line L3 (219.5, 92) -> (219.5, 80)
  dimension "d3215" = 219.5
  dimension "d3216" = 80
  dimension "d3217" = 2.7
  dimension "d3218" = 12
  constraint horizontal L0
  constraint vertical L1
  constraint horizontal L2
  constraint vertical L3
  measures "d3215" horizontal distance of origin L0.start
  measures "d3216" vertical distance of origin L0.start
  measures "d3217" horizontal distance of L0.start L0.end
  measures "d3218" vertical distance of L0.end L1.end
extrude "Thin nut envelope''''''''''''''''''''''''''''''" add sketch "Thin nut envelope sketch (31)" along normal blind 8.8 separate body makes body 113 in component "REFERENCE thin METAL channel nut side wall 101"
ref_plane "WorkPlane2" through (219.5, 0, 0) normal (1, 0, 0) x (0, 1, 0) in component "REFERENCE thin METAL channel nut side wall 101"
sketch "Thread envelope sketch (31)" plane through (219.5, 0, 0) normal (1, 0, 0) x (0, 0, -1) in component "REFERENCE thin METAL channel nut side wall 101"
  circle A0 centre (-25, 86) radius 2.6
  dimension "d3223" = 25
  dimension "d3224" = 86
  dimension "d3225" = 5.2
  measures "d3223" horizontal distance of origin A0.centre
  measures "d3224" vertical distance of origin A0.centre
  measures "d3225" diameter of A0
extrude "Thread envelope''''''''''''''''''''''''''''''" cut sketch "Thread envelope sketch (31)" along normal blind 2.7 bodies 113 in component "REFERENCE thin METAL channel nut side wall 101"
ref_plane "WorkPlane5" through (0, 0, 32) normal (0, 0, 1) x (1, 0, 0) in component "METAL flush wall tab 10"
sketch "Wall anchor clearance sketch (3)" plane through (0, 0, 32) normal (0, 0, 1) x (1, 0, 0) in component "METAL flush wall tab 10"
  circle A0 centre (205, 80) radius 3.25
  dimension "d3230" = 205
  dimension "d3231" = 80
  dimension "d3232" = 6.5
  measures "d3230" horizontal distance of origin A0.centre
  measures "d3231" vertical distance of origin A0.centre
  measures "d3232" diameter of A0
extrude "Wall anchor clearance''" cut sketch "Wall anchor clearance sketch (3)" along normal blind 3 bodies 109 in component "METAL flush wall tab 10"
ref_plane "WorkPlane1" through (0, 0, 29) normal (0, 0, 1) x (1, 0, 0) in component "REFERENCE wall anchor HEAD ONLY 10"
sketch "Anchor head envelope sketch (3)" plane through (0, 0, 29) normal (0, 0, 1) x (1, 0, 0) in component "REFERENCE wall anchor HEAD ONLY 10"
  circle A0 centre (205, 80) radius 6
  dimension "d3237" = 205
  dimension "d3238" = 80
  dimension "d3239" = 12
  measures "d3237" horizontal distance of origin A0.centre
  measures "d3238" vertical distance of origin A0.centre
  measures "d3239" diameter of A0
extrude "Anchor head envelope''" add sketch "Anchor head envelope sketch (3)" along normal blind 3 separate body makes body 114 in component "REFERENCE wall anchor HEAD ONLY 10"
ref_plane "WorkPlane2" through (0, 0, 32) normal (0, 0, 1) x (1, 0, 0) in component "REFERENCE wall anchor HEAD ONLY 10"
sketch "Clearance shank only - anchor not selected sketch (3)" plane through (0, 0, 32) normal (0, 0, 1) x (1, 0, 0) in component "REFERENCE wall anchor HEAD ONLY 10"
  circle A0 centre (205, 80) radius 3
  dimension "d3244" = 205
  dimension "d3245" = 80
  dimension "d3246" = 6
  measures "d3244" horizontal distance of origin A0.centre
  measures "d3245" vertical distance of origin A0.centre
  measures "d3246" diameter of A0
extrude "Clearance shank only - anchor not selected''" add sketch "Clearance shank only - anchor not selected sketch (3)" along normal blind 3 bodies 114 in component "REFERENCE wall anchor HEAD ONLY 10"
ref_plane "WorkPlane1" through (0, 0, 15) normal (0, 0, 1) x (1, 0, 0) in component "METAL flush wall tab 11"
sketch "Side attachment leg sketch (4)" plane through (0, 0, 15) normal (0, 0, 1) x (1, 0, 0) in component "METAL flush wall tab 11"
  line L0 (215, 148) -> (218, 148)
  line L1 (218, 148) -> (218, 172)
  line L2 (218, 172) -> (215, 172)
  line L3 (215, 172) -> (215, 148)
  dimension "d3251" = 215
  dimension "d3252" = 148
  dimension "d3253" = 3
  dimension "d3254" = 24
  constraint horizontal L0
  constraint vertical L1
  constraint horizontal L2
  constraint vertical L3
  measures "d3251" horizontal distance of origin L0.start
  measures "d3252" vertical distance of origin L0.start
  measures "d3253" horizontal distance of L0.start L0.end
  measures "d3254" vertical distance of L0.end L1.end
extrude "Side attachment leg'''" add sketch "Side attachment leg sketch (4)" along normal blind 20 separate body makes body 115 in component "METAL flush wall tab 11"
ref_plane "WorkPlane2" through (0, 0, 32) normal (0, 0, 1) x (1, 0, 0) in component "METAL flush wall tab 11"
sketch "Flush wall foot sketch (4)" plane through (0, 0, 32) normal (0, 0, 1) x (1, 0, 0) in component "METAL flush wall tab 11"
  line L0 (196, 148) -> (218, 148)
  line L1 (218, 148) -> (218, 172)
  line L2 (218, 172) -> (196, 172)
  line L3 (196, 172) -> (196, 148)
  dimension "d3259" = 196
  dimension "d3260" = 148
  dimension "d3261" = 22
  dimension "d3262" = 24
  constraint horizontal L0
  constraint vertical L1
  constraint horizontal L2
  constraint vertical L3
  measures "d3259" horizontal distance of origin L0.start
  measures "d3260" vertical distance of origin L0.start
  measures "d3261" horizontal distance of L0.start L0.end
  measures "d3262" vertical distance of L0.end L1.end
extrude "Flush wall foot'''" add sketch "Flush wall foot sketch (4)" along normal blind 3 bodies 115 in component "METAL flush wall tab 11"
ref_plane "WorkPlane3" through (218, 0, 0) normal (1, 0, 0) x (0, 1, 0) in component "METAL flush wall tab 11"
sketch "Side fixing sketch (4)" plane through (218, 0, 0) normal (1, 0, 0) x (0, 0, -1) in component "METAL flush wall tab 11"
  circle A0 centre (-25, 154) radius 2.75
  dimension "d3267" = 25
  dimension "d3268" = 154
  dimension "d3269" = 5.5
  measures "d3267" horizontal distance of origin A0.centre
  measures "d3268" vertical distance of origin A0.centre
  measures "d3269" diameter of A0
extrude "Side fixing'''" cut sketch "Side fixing sketch (4)" against normal blind 3 bodies 115 in component "METAL flush wall tab 11"
ref_plane "WorkPlane1" through (215, 0, 0) normal (1, 0, 0) x (0, 1, 0) in component "REFERENCE side M5x8 wall 110"
sketch "Button head envelope sketch (32)" plane through (215, 0, 0) normal (1, 0, 0) x (0, 0, -1) in component "REFERENCE side M5x8 wall 110"
  circle A0 centre (-25, 154) radius 4.75
  dimension "d3274" = 25
  dimension "d3275" = 154
  dimension "d3276" = 9.5
  measures "d3274" horizontal distance of origin A0.centre
  measures "d3275" vertical distance of origin A0.centre
  measures "d3276" diameter of A0
extrude "Button head envelope'''''''''''''''''''''''''''''''" add sketch "Button head envelope sketch (32)" against normal blind 3 separate body makes body 116 in component "REFERENCE side M5x8 wall 110"
ref_plane "WorkPlane2" through (215, 0, 0) normal (1, 0, 0) x (0, 1, 0) in component "REFERENCE side M5x8 wall 110"
sketch "Shank envelope sketch (32)" plane through (215, 0, 0) normal (1, 0, 0) x (0, 0, -1) in component "REFERENCE side M5x8 wall 110"
  circle A0 centre (-25, 154) radius 2.5
  dimension "d3281" = 25
  dimension "d3282" = 154
  dimension "d3283" = 5
  measures "d3281" horizontal distance of origin A0.centre
  measures "d3282" vertical distance of origin A0.centre
  measures "d3283" diameter of A0
extrude "Shank envelope'''''''''''''''''''''''''''''''" add sketch "Shank envelope sketch (32)" along normal blind 8 bodies 116 in component "REFERENCE side M5x8 wall 110"
ref_plane "WorkPlane1" through (0, 0, 20.6) normal (0, 0, 1) x (1, 0, 0) in component "REFERENCE thin METAL channel nut side wall 110"